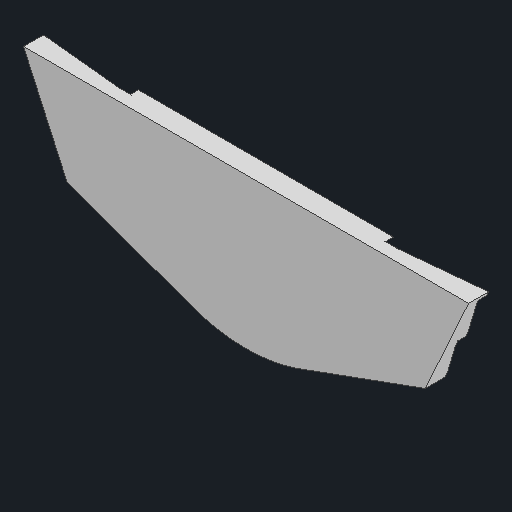
# Autodesk Inventor part: 7_3_3_grille_avant
Saved by Autodesk Inventor 2026 (Build 300175000, 175)
## iProperties
Created: 2025-06-21
Part Number: 7_3_3_grille_avant
Material: Generic
Document SubType Name: Modeling
Designer: remg9
Density: 1 g/cm^3
Appearance: Default
Author: remg9
Autodesk Inventor part; units mm, degrees
ref_plane "YZ Plane" through (0, 0, 0) normal (1, 0, 0) x (0, 1, 0)
ref_plane "XZ Plane" through (0, 0, 0) normal (0, 1, 0) x (-1, 0, 0)
ref_plane "XY Plane" through (0, 0, 0) normal (0, 0, 1) x (1, 0, 0)
sketch "Sketch1" plane through (0, 0, 0) normal (0, 0, 1) x (1, 0, 0)
  line L0 (56, 40.4117) -> (45.0909, 16.4117)
  line L1 (45.0909, 16.4117) -> (0, 0)
  line L2 (45.0909, 16.4117) -> (0, 16.4117) construction
  line L3 (0, 0) -> (0, 41.4117) construction
  line L4 (0, 41.4117) -> (58, 41.4117) construction
  line L5 (58, 41.4117) -> (48, 19.4117) construction
  line L6 (56, 40.4117) -> (0, 40.4117)
  line L7 (-56, 40.4117) -> (-45.0909, 16.4117)
  line L8 (-45.0909, 16.4117) -> (0, 0)
  line L9 (-45.0909, 16.4117) -> (0, 16.4117) construction
  line L10 (0, 41.4117) -> (-58, 41.4117) construction
  line L11 (-58, 41.4117) -> (-48, 19.4117) construction
  line L12 (-56, 40.4117) -> (0, 40.4117)
  dimension "d5" = 20
  dimension "d8" = 10
  dimension "d9" = 22
  dimension "d10" = 56
  dimension "d12" = 24
  dimension "d13" = 1
  dimension "d14" = 58
  dimension "d16" = 1.4069
  constraints: 27 end point, 4 symmetric about line, 2 coincident, 2 horizontal, 2 perpendicular, 2 point on line, 1 parallel
  measures "d5" angle of L2 L1
  measures "d8" horizontal distance of L4.end L5.end
  measures "d9" vertical distance of L4.end L5.end
  measures "d10" distance of L0.start L6.end
  measures "d12" distance from line of L6 L0.end
  measures "d13" distance between parallel lines of L6 L4
  measures "d14" distance of L3.end L4.end
  measures "d16" distance between parallel lines of L0 L5
extrude "Extrusion1" add sketch "Sketch1" along normal blind 5
fillet "Fillet1" radius 40 1 edges at (0, 0, 2.5)
sketch "Sketch3" plane through (0, 0, 0) normal (0, 0, -1) x (-1, 0, 0)
  line L0 (-61.0823, 49.9008) -> (-13.6808, 32.648)
  line L1 (13.6808, 32.648) -> (61.0823, 49.9008)
  line L2 (61.0823, 49.9008) -> (60.7403, 50.8405)
  line L3 (60.7403, 50.8405) -> (13.6808, 33.7122)
  line L4 (-13.6808, 33.7122) -> (-60.7403, 50.8405)
  line L5 (-60.7403, 50.8405) -> (-61.0823, 49.9008)
  line L6 (45.0909, 16.4117) -> (13.6808, 4.9794) projected
  line L7 (-13.6808, 4.9794) -> (-45.0909, 16.4117) projected
  line L8 (56, 40.4117) -> (45.0909, 16.4117) projected
  line L9 (-45.0909, 16.4117) -> (-56, 40.4117) projected
  arc A0 (-0.684, 28.9818) -> (0.684, 28.9818) centre (0, 30.8612) ccw
  arc A1 (-13.6808, 33.7122) -> (13.6808, 33.7122) centre (0, 71.2999) ccw
  arc A2 (-13.6808, 32.648) -> (13.6808, 32.648) centre (0, 70.2357) ccw
  line L10 (-50.6494, 26.9483) -> (-13.6808, 13.4928)
  line L11 (13.6808, 13.4928) -> (50.1886, 26.7806)
  line L12 (50.1886, 26.7806) -> (49.8466, 27.7203)
  line L13 (49.8466, 27.7203) -> (13.6808, 14.557)
  line L14 (-13.6808, 14.557) -> (-50.3074, 27.888)
  line L15 (-50.3074, 27.888) -> (-50.6494, 26.9483)
  arc A3 (-0.684, 9.8266) -> (0.684, 9.8266) centre (0, 11.706) ccw
  arc A4 (-13.6808, 14.557) -> (13.6808, 14.557) centre (0, 52.1447) ccw
  arc A5 (-13.6808, 13.4928) -> (13.6808, 13.4928) centre (0, 51.0805) ccw
  line L16 (-55.8659, 38.4245) -> (-13.6808, 23.0704)
  line L17 (13.6808, 23.0704) -> (55.8659, 38.4245)
  line L18 (55.8659, 38.4245) -> (55.5239, 39.3642)
  line L19 (55.5239, 39.3642) -> (13.6808, 24.1346)
  line L20 (-13.6808, 24.1346) -> (-55.5239, 39.3642)
  arc A6 (-0.684, 19.4042) -> (0.684, 19.4042) centre (0, 21.2836) ccw
  arc A7 (-13.6808, 24.1346) -> (13.6808, 24.1346) centre (0, 61.7223) ccw
  arc A8 (-13.6808, 23.0704) -> (13.6808, 23.0704) centre (0, 60.6581) ccw
  line L21 (0, 40.4117) -> (0, 2.5671) construction
  line L22 (-56, 40.4117) -> (56, 40.4117) construction
  arc A9 (-13.6808, 4.9794) -> (13.6808, 4.9794) centre (0, 42.5671) ccw construction
  line L23 (-55.5239, 39.3642) -> (-55.8659, 38.4245)
  point P0 (0, 0)
  point P1 (50.0176, 27.2504)
  point P2 (54.9442, 38.0891)
  point P3 (-54.9442, 38.0891)
  dimension "d20" = 1
  dimension "d21" = 1
  dimension "d22" = 2
  dimension "d23" = 40
  dimension "d24" = 40
  dimension "d25" = 1
  dimension "d26" = 1
  dimension "d27" = 2
  dimension "d28" = 40
  dimension "d29" = 40
  dimension "d30" = 1
  dimension "d31" = 1
  dimension "d32" = 2
  dimension "d33" = 40
  dimension "d34" = 40
  dimension "d35" = 8
  dimension "d36" = 8
  dimension "d37" = 8
  constraints: 38 end point, 19 point on circle, 18 tangent, 15 point on line, 9 centre point, 9 parallel, 9 perpendicular, 2 midpoint, 1 vertical
  measures "d20" distance between parallel lines of L0 L4
  measures "d21" distance between parallel lines of L1 L3
  measures "d22" radius of A0
  measures "d23" radius of A1
  measures "d24" radius of A2
  measures "d25" distance between parallel lines of L10 L14
  measures "d26" distance between parallel lines of L11 L13
  measures "d27" radius of A3
  measures "d28" radius of A4
  measures "d29" radius of A5
  measures "d30" distance between parallel lines of L16 L20
  measures "d31" distance between parallel lines of L17 L19
  measures "d32" radius of A6
  measures "d33" radius of A7
  measures "d34" radius of A8
  measures "d35" distance between parallel lines of L6 L11
  measures "d36" distance between parallel lines of L13 L17
  measures "d37" distance between parallel lines of L19 L1
extrude "Extrusion2" cut sketch "Sketch3" against normal blind 2 contours L5 L4 A1 L3 L2 L1 A2 L0 | L8 L17 A8 L16 L9 L20 A7 L19 | L12 L11 L8 | L8 L11 A5 L10 L9 L14 A4 L13 L12 | L9 L10 L15
chamfer "Chamfer1" distance 7 distance2 2 3 edges at (0, 30.2357, 0) (24.3461, 36.5299, 0) (-24.3461, 36.5299, 0) measured on face at (34.7387, 34.6369, 0)
chamfer "Chamfer2" distance 7 distance2 2 3 edges at (0, 20.6581, 0) (34.3125, 30.5798, 0) (-34.3125, 30.5798, 0) measured on face at (39.6441, 29.6825, 0)
chamfer "Chamfer3" distance 7 distance2 2 3 edges at (0, 11.0805, 0) (31.7043, 20.0528, 0) (-31.7043, 20.0528, 0) measured on face at (-36.1665, 18.8391, 0)
sketch "Sketch4" plane through (0, 0, 0) normal (0, 0, -1) x (-1, 0, 0)
  line L0 (-11.1103, 39.4117) -> (11.1949, 39.4117) construction
  line L1 (11.1949, 39.4117) -> (11.1949, 33.173) construction
  line L2 (11.1949, 33.173) -> (-11.1103, 33.173) construction
  line L3 (-11.1103, 33.173) -> (-11.1103, 39.4117) construction
  line L4 (-32.0876, 40.4117) -> (32.0876, 40.4117) projected
  line L5 (0.0423, 40.038) -> (0.0423, 32.6492) construction
  line L6 (-4.8422, 33.3117) -> (-6.7058, 33.3117)
  line L7 (-6.7058, 33.3117) -> (-8.4014, 35.5511)
  line L8 (-8.4014, 35.5511) -> (-8.955, 35.5511)
  line L9 (-8.955, 35.5511) -> (-8.955, 33.3117)
  line L10 (-8.955, 33.3117) -> (-10.4775, 33.3117)
  line L11 (-10.4775, 33.3117) -> (-10.4775, 39.4117)
  line L12 (-10.4775, 39.4117) -> (-8.0257, 39.4117)
  spline S0 degree 2 poles (-8.0257, 39.4117) (-7.5165, 39.4117) (-6.7651, 39.2832) (-6.4438, 39.0855) knots 0 0 0 1 2 2 2
  spline S1 degree 2 poles (-6.4438, 39.0855) (-6.1176, 38.8779) (-5.732, 38.2303) (-5.732, 37.736) knots 0 0 0 1 2 2 2
  spline S2 degree 2 poles (-5.732, 37.736) (-5.732, 37.039) (-6.3647, 36.164) (-6.8937, 35.907) knots 0 0 0 1 2 2 2
  line L13 (-6.8937, 35.907) -> (-4.8422, 33.3117)
  spline S3 degree 2 poles (-7.304, 37.5432) (-7.304, 37.7755) (-7.4819, 38.1067) (-7.6846, 38.1957) knots 0 0 0 1 2 2 2
  spline S4 degree 2 poles (-7.6846, 38.1957) (-7.828, 38.255) (-8.1789, 38.2896) (-8.4409, 38.2896) knots 0 0 0 1 2 2 2
  line L14 (-8.4409, 38.2896) -> (-8.955, 38.2896)
  line L15 (-8.955, 38.2896) -> (-8.955, 36.6485)
  line L16 (-8.955, 36.6485) -> (-8.5151, 36.6485)
  spline S5 degree 2 poles (-8.5151, 36.6485) (-8.1987, 36.6485) (-7.7489, 36.7276) (-7.5956, 36.8511) knots 0 0 0 1 2 2 2
  spline S6 degree 2 poles (-7.5956, 36.8511) (-7.4473, 36.9698) (-7.304, 37.2861) (-7.304, 37.5432) knots 0 0 0 1 2 2 2
  line L17 (0.7041, 39.4117) -> (-1.3918, 33.3117)
  line L18 (-1.3918, 33.3117) -> (-2.9885, 33.3117)
  line L19 (-2.9885, 33.3117) -> (-5.0844, 39.4117)
  line L20 (-5.0844, 39.4117) -> (-3.4976, 39.4117)
  line L21 (-3.4976, 39.4117) -> (-2.1679, 35.2742)
  line L22 (-2.1679, 35.2742) -> (-0.8431, 39.4117)
  line L23 (-0.8431, 39.4117) -> (0.7041, 39.4117)
  line L24 (1.2726, 33.3117) -> (1.2726, 39.4117)
  line L25 (1.2726, 39.4117) -> (5.3953, 39.4117)
  line L26 (5.3953, 39.4117) -> (5.3953, 38.2501)
  line L27 (5.3953, 38.2501) -> (2.7951, 38.2501)
  line L28 (2.7951, 38.2501) -> (2.7951, 37.1774)
  line L29 (2.7951, 37.1774) -> (5.1926, 37.1774)
  line L30 (5.1926, 37.1774) -> (5.1926, 36.0157)
  line L31 (5.1926, 36.0157) -> (2.7951, 36.0157)
  line L32 (2.7951, 36.0157) -> (2.7951, 34.4734)
  line L33 (2.7951, 34.4734) -> (5.3953, 34.4734)
  line L34 (5.3953, 34.4734) -> (5.3953, 33.3117)
  line L35 (5.3953, 33.3117) -> (1.2726, 33.3117)
  line L36 (10.8576, 33.3117) -> (6.0231, 33.3117)
  line L37 (6.0231, 33.3117) -> (6.0231, 34.4536)
  line L38 (6.0231, 34.4536) -> (8.8358, 38.2501)
  line L39 (8.8358, 38.2501) -> (6.1714, 38.2501)
  line L40 (6.1714, 38.2501) -> (6.1714, 39.4117)
  line L41 (6.1714, 39.4117) -> (10.6945, 39.4117)
  line L42 (10.6945, 39.4117) -> (10.6945, 38.2501)
  line L43 (10.6945, 38.2501) -> (7.8917, 34.4734)
  line L44 (7.8917, 34.4734) -> (10.8576, 34.4734)
  line L45 (10.8576, 34.4734) -> (10.8576, 33.3117)
  point P0 (0, 0)
  point P1 (0.0423, 39.4117)
  dimension "d49" = 1
  constraints: 2 end point, 1 midpoint, 1 point on line, 1 vertical, 2 other
  measures "d49" distance between parallel lines of L4 L0
extrude "Extrusion3" cut sketch "Sketch4" against normal blind 1
body "Solid1"
